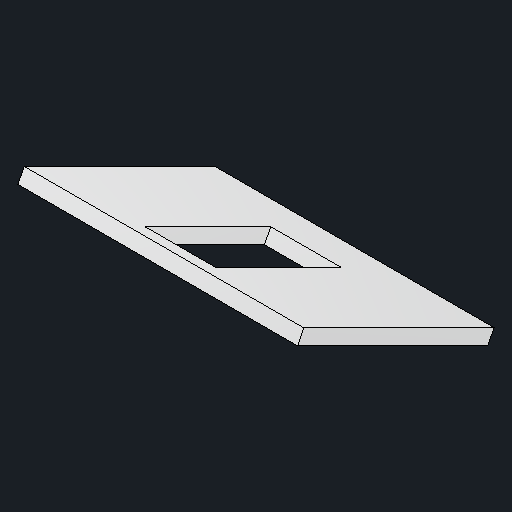
# Autodesk Inventor part: Echelle support roof plate
Saved by Autodesk Inventor 2027.1 (Build 311270010, 270A)
## iProperties
Created: 2026-11-21
Part Number: Echelle support roof plate
Material: Aluminum 6061
Description: Echelle support roof plate; photo-based dimensional mockup, verify before fabrication
Document SubType Name: Modeling
Designer: queezz
Density: 2.7 g/cm^3
Appearance: Aluminum - Flat
Mass: 685.69 g
Surface Area: 608.315 cm^2
Volume: 253.959 cm^3
Author: queezz
Autodesk Inventor part; units mm, degrees
ref_plane "XZ Plane" through (0, 0, 0) normal (0, 1, 0) x (-1, 0, 0)
ref_plane "XY Plane" through (0, 0, 0) normal (0, 0, 1) x (1, 0, 0)
ref_plane "Centered grating opening plane" through (75, 0, 0) normal (1, 0, 0) x (0, 1, 0)
sketch "Roof section - square lower end extended to side cut" plane through (0, 0, 0) normal (1, 0, 0) x (0, 1, 0)
  line L0 (36.1353, -4.462) -> (103.9483, 131.5499)
  line L1 (103.9483, 131.5499) -> (94.999, 136.0118)
  line L2 (94.999, 136.0118) -> (27.186, 0)
  line L3 (27.186, 0) -> (36.1353, -4.462)
  point P0 (0, 0)
  dimension "d40" = 36.1353
  dimension "d41" = 4.462
  dimension "d42" = 103.9483
  dimension "d43" = 131.5499
  dimension "d44" = 94.999
  dimension "d45" = 136.0119
  dimension "d46" = 27.186
  constraints: 8 end point, 1 horizontal alignment, 1 other
  measures "d40" horizontal distance of point (0, 0) L0.start
  measures "d41" vertical distance of point (0, 0) L0.start
  measures "d42" horizontal distance of point (0, 0) L0.end
  measures "d43" vertical distance of point (0, 0) L0.end
  measures "d44" horizontal distance of point (0, 0) L1.end
  measures "d45" vertical distance of point (0, 0) L1.end
  measures "d46" distance of point (0, 0) L2.end
extrude "Square edged window plate" add sketch "Roof section - square lower end extended to side cut" along normal blind 200
sketch "Grating opening - square through plate" plane through (75, 0, 0) normal (1, 0, 0) x (0, 1, 0)
  line L0 (57.9184, 28.0223) -> (40.0197, 36.9462)
  line L1 (40.0197, 36.9462) -> (84.6395, 126.4397)
  line L2 (84.6395, 126.4397) -> (102.5382, 117.5157)
  line L3 (102.5382, 117.5157) -> (57.9184, 28.0223)
  point P0 (0, 0)
  dimension "d49" = 57.9184
  dimension "d50" = 28.0223
  dimension "d51" = 40.0197
  dimension "d52" = 36.9462
  dimension "d53" = 84.6395
  dimension "d54" = 126.4397
  dimension "d55" = 102.5382
  dimension "d56" = 117.5157
  constraints: 8 end point, 1 other
  measures "d49" horizontal distance of point (0, 0) L0.start
  measures "d50" vertical distance of point (0, 0) L0.start
  measures "d51" horizontal distance of point (0, 0) L0.end
  measures "d52" vertical distance of point (0, 0) L0.end
  measures "d53" horizontal distance of point (0, 0) L1.end
  measures "d54" vertical distance of point (0, 0) L1.end
  measures "d55" horizontal distance of point (0, 0) L2.end
  measures "d56" vertical distance of point (0, 0) L2.end
extrude "Through grating opening" cut sketch "Grating opening - square through plate" along normal blind 50
equation "\"d42\" = RoofEndDepth"
equation "\"d43\" = RoofEndHeight"
equation "\"d47\" = SupportWidth"
equation "\"d57\" = WindowWidth"
equation "\"d10\" = -0.5 * WindowWidth + 0.5 * SupportWidth"
equation "\"SupportWidth\" = 200"
equation "\"WindowWidth\" = 50"
equation "\"RoofEndDepth\" = 103.948344"
equation "\"RoofEndHeight\" = 131.549867"
body "Solid3"
